Autodesk Fusion 360 part; units mm, degrees
(part 2 of 2)
extrude "CUT-SK-1100-04_M2_RAIL_TAP_A04" cut sketch "SK-1100-04_M2_RAIL_TAP_A04" against normal blind 4 contours A10 bodies 1 in component "CBP-1100_BASE_PLATE"
sketch "SK-1100-04_M2_RAIL_TAP_B04" plane through (0, 12, 0) normal (0, 1, 0) x (0, 0, 1) in component "CBP-1100_BASE_PLATE"
  circle A0 centre (60, -30) radius 0.8
  circle A1 centre (60, -45) radius 0.8
  circle A2 centre (110, 130) radius 4.5
  circle A3 centre (-110, -130) radius 4.5
  circle A4 centre (110, -130) radius 4.5
  circle A5 centre (-110, 130) radius 4.5
  line L0 (49, 74) -> (49, -74)
  line L1 (49, -74) -> (-49, -74)
  line L2 (-49, -74) -> (-49, 74)
  line L3 (-49, 74) -> (49, 74)
  line L4 (130, 150) -> (-130, 150)
  line L5 (-130, 150) -> (-130, -150)
  line L6 (-130, -150) -> (130, -150)
  line L7 (130, -150) -> (130, 150)
  circle A6 centre (-60, -60) radius 0.8
  circle A7 centre (60, -60) radius 0.8
  circle A8 centre (-60, -45) radius 0.8
  circle A9 centre (-60, -30) radius 0.8
  circle A10 centre (-60, -15) radius 0.8
  circle A11 centre (60, -15) radius 0.8
  dimension "d424" = 60
  dimension "d425" = 15
  dimension "d426" = 1.6
  measures "d424" horizontal distance of origin A11.centre
  measures "d425" vertical distance of origin A11.centre
  measures "d426" diameter of A11
extrude "CUT-SK-1100-04_M2_RAIL_TAP_B04" cut sketch "SK-1100-04_M2_RAIL_TAP_B04" against normal blind 4 contours A11 bodies 1 in component "CBP-1100_BASE_PLATE"
sketch "SK-1300-02_RAIL_CLEAR_05" plane through (0, 0, 0) normal (0, 1, 0) x (1, 0, 0) in component "CBP-1300_X_RAIL_ALIGNMENT_SHIM"
  circle A0 centre (0, 0) radius 1.15
  dimension "d429" = 2.3
  constraint coincident A0.centre origin
  measures "d429" diameter of A0
extrude "CUT-SK-1300-02_RAIL_CLEAR_05" cut sketch "SK-1300-02_RAIL_CLEAR_05" along normal blind 2 bodies 12 in component "CBP-1300_X_RAIL_ALIGNMENT_SHIM"
sketch "SK-1100-04_M2_RAIL_TAP_A05" plane through (0, 12, 0) normal (0, 1, 0) x (0, 0, 1) in component "CBP-1100_BASE_PLATE"
  circle A0 centre (-60, -15) radius 0.8
  circle A1 centre (-60, -30) radius 0.8
  circle A2 centre (-60, -45) radius 0.8
  circle A3 centre (60, -60) radius 0.8
  circle A4 centre (-60, -60) radius 0.8
  line L0 (130, 150) -> (-130, 150)
  line L1 (-130, 150) -> (-130, -150)
  line L2 (-130, -150) -> (130, -150)
  line L3 (130, -150) -> (130, 150)
  line L4 (49, 74) -> (49, -74)
  line L5 (49, -74) -> (-49, -74)
  line L6 (-49, -74) -> (-49, 74)
  line L7 (-49, 74) -> (49, 74)
  circle A5 centre (-110, 130) radius 4.5
  circle A6 centre (110, -130) radius 4.5
  circle A7 centre (-110, -130) radius 4.5
  circle A8 centre (110, 130) radius 4.5
  circle A9 centre (60, -45) radius 0.8
  circle A10 centre (60, -30) radius 0.8
  circle A11 centre (60, -15) radius 0.8
  circle A12 centre (-60, 0) radius 0.8
  dimension "d432" = 60
  dimension "d433" = 1.6
  constraint horizontal origin A12.centre
  measures "d432" horizontal distance of origin A12.centre
  measures "d433" diameter of A12
extrude "CUT-SK-1100-04_M2_RAIL_TAP_A05" cut sketch "SK-1100-04_M2_RAIL_TAP_A05" against normal blind 4 contours A12 bodies 1 in component "CBP-1100_BASE_PLATE"
sketch "SK-1100-04_M2_RAIL_TAP_B05" plane through (0, 12, 0) normal (0, 1, 0) x (0, 0, 1) in component "CBP-1100_BASE_PLATE"
  circle A0 centre (60, -15) radius 0.8
  circle A1 centre (60, -30) radius 0.8
  circle A2 centre (60, -45) radius 0.8
  circle A3 centre (110, 130) radius 4.5
  circle A4 centre (-110, -130) radius 4.5
  circle A5 centre (110, -130) radius 4.5
  circle A6 centre (-110, 130) radius 4.5
  line L0 (49, 74) -> (49, -74)
  line L1 (49, -74) -> (-49, -74)
  line L2 (-49, -74) -> (-49, 74)
  line L3 (-49, 74) -> (49, 74)
  line L4 (130, 150) -> (-130, 150)
  line L5 (-130, 150) -> (-130, -150)
  line L6 (-130, -150) -> (130, -150)
  line L7 (130, -150) -> (130, 150)
  circle A7 centre (-60, -60) radius 0.8
  circle A8 centre (60, -60) radius 0.8
  circle A9 centre (-60, -45) radius 0.8
  circle A10 centre (-60, -30) radius 0.8
  circle A11 centre (-60, -15) radius 0.8
  circle A12 centre (-60, 0) radius 0.8
  circle A13 centre (60, 0) radius 0.8
  dimension "d436" = 60
  dimension "d437" = 1.6
  constraint horizontal origin A13.centre
  measures "d436" horizontal distance of origin A13.centre
  measures "d437" diameter of A13
extrude "CUT-SK-1100-04_M2_RAIL_TAP_B05" cut sketch "SK-1100-04_M2_RAIL_TAP_B05" against normal blind 4 contours A13 bodies 1 in component "CBP-1100_BASE_PLATE"
sketch "SK-1300-02_RAIL_CLEAR_06" plane through (0, 0, 0) normal (0, 1, 0) x (1, 0, 0) in component "CBP-1300_X_RAIL_ALIGNMENT_SHIM"
  circle A0 centre (15, 0) radius 1.15
  dimension "d440" = 15
  dimension "d441" = 2.3
  constraint horizontal origin A0.centre
  measures "d440" horizontal distance of origin A0.centre
  measures "d441" diameter of A0
extrude "CUT-SK-1300-02_RAIL_CLEAR_06" cut sketch "SK-1300-02_RAIL_CLEAR_06" along normal blind 2 bodies 12 in component "CBP-1300_X_RAIL_ALIGNMENT_SHIM"
sketch "SK-1100-04_M2_RAIL_TAP_A06" plane through (0, 12, 0) normal (0, 1, 0) x (0, 0, 1) in component "CBP-1100_BASE_PLATE"
  circle A0 centre (-60, 0) radius 0.8
  circle A1 centre (-60, -15) radius 0.8
  circle A2 centre (-60, -30) radius 0.8
  circle A3 centre (-60, -45) radius 0.8
  circle A4 centre (60, -60) radius 0.8
  circle A5 centre (-60, -60) radius 0.8
  line L0 (130, 150) -> (-130, 150)
  line L1 (-130, 150) -> (-130, -150)
  line L2 (-130, -150) -> (130, -150)
  line L3 (130, -150) -> (130, 150)
  line L4 (49, 74) -> (49, -74)
  line L5 (49, -74) -> (-49, -74)
  line L6 (-49, -74) -> (-49, 74)
  line L7 (-49, 74) -> (49, 74)
  circle A6 centre (-110, 130) radius 4.5
  circle A7 centre (110, -130) radius 4.5
  circle A8 centre (-110, -130) radius 4.5
  circle A9 centre (110, 130) radius 4.5
  circle A10 centre (60, -45) radius 0.8
  circle A11 centre (60, -30) radius 0.8
  circle A12 centre (60, -15) radius 0.8
  circle A13 centre (60, 0) radius 0.8
  circle A14 centre (-60, 15) radius 0.8
  dimension "d444" = 60
  dimension "d445" = 15
  dimension "d446" = 1.6
  measures "d444" horizontal distance of origin A14.centre
  measures "d445" vertical distance of origin A14.centre
  measures "d446" diameter of A14
extrude "CUT-SK-1100-04_M2_RAIL_TAP_A06" cut sketch "SK-1100-04_M2_RAIL_TAP_A06" against normal blind 4 contours A14 bodies 1 in component "CBP-1100_BASE_PLATE"
sketch "SK-1100-04_M2_RAIL_TAP_B06" plane through (0, 12, 0) normal (0, 1, 0) x (0, 0, 1) in component "CBP-1100_BASE_PLATE"
  circle A0 centre (60, 0) radius 0.8
  circle A1 centre (60, -15) radius 0.8
  circle A2 centre (60, -30) radius 0.8
  circle A3 centre (60, -45) radius 0.8
  circle A4 centre (110, 130) radius 4.5
  circle A5 centre (-110, -130) radius 4.5
  circle A6 centre (110, -130) radius 4.5
  circle A7 centre (-110, 130) radius 4.5
  line L0 (49, 74) -> (49, -74)
  line L1 (49, -74) -> (-49, -74)
  line L2 (-49, -74) -> (-49, 74)
  line L3 (-49, 74) -> (49, 74)
  line L4 (130, 150) -> (-130, 150)
  line L5 (-130, 150) -> (-130, -150)
  line L6 (-130, -150) -> (130, -150)
  line L7 (130, -150) -> (130, 150)
  circle A8 centre (-60, -60) radius 0.8
  circle A9 centre (60, -60) radius 0.8
  circle A10 centre (-60, -45) radius 0.8
  circle A11 centre (-60, -30) radius 0.8
  circle A12 centre (-60, -15) radius 0.8
  circle A13 centre (-60, 0) radius 0.8
  circle A14 centre (-60, 15) radius 0.8
  circle A15 centre (60, 15) radius 0.8
  dimension "d449" = 60
  dimension "d450" = 15
  dimension "d451" = 1.6
  measures "d449" horizontal distance of origin A15.centre
  measures "d450" vertical distance of origin A15.centre
  measures "d451" diameter of A15
extrude "CUT-SK-1100-04_M2_RAIL_TAP_B06" cut sketch "SK-1100-04_M2_RAIL_TAP_B06" against normal blind 4 contours A15 bodies 1 in component "CBP-1100_BASE_PLATE"
sketch "SK-1300-02_RAIL_CLEAR_07" plane through (0, 0, 0) normal (0, 1, 0) x (1, 0, 0) in component "CBP-1300_X_RAIL_ALIGNMENT_SHIM"
  circle A0 centre (30, 0) radius 1.15
  dimension "d454" = 30
  dimension "d455" = 2.3
  constraint horizontal origin A0.centre
  measures "d454" horizontal distance of origin A0.centre
  measures "d455" diameter of A0
extrude "CUT-SK-1300-02_RAIL_CLEAR_07" cut sketch "SK-1300-02_RAIL_CLEAR_07" along normal blind 2 bodies 12 in component "CBP-1300_X_RAIL_ALIGNMENT_SHIM"
sketch "SK-1100-04_M2_RAIL_TAP_A07" plane through (0, 12, 0) normal (0, 1, 0) x (0, 0, 1) in component "CBP-1100_BASE_PLATE"
  circle A0 centre (-60, 15) radius 0.8
  circle A1 centre (-60, 0) radius 0.8
  circle A2 centre (-60, -15) radius 0.8
  circle A3 centre (-60, -30) radius 0.8
  circle A4 centre (-60, -45) radius 0.8
  circle A5 centre (60, -60) radius 0.8
  circle A6 centre (-60, -60) radius 0.8
  line L0 (130, 150) -> (-130, 150)
  line L1 (-130, 150) -> (-130, -150)
  line L2 (-130, -150) -> (130, -150)
  line L3 (130, -150) -> (130, 150)
  line L4 (49, 74) -> (49, -74)
  line L5 (49, -74) -> (-49, -74)
  line L6 (-49, -74) -> (-49, 74)
  line L7 (-49, 74) -> (49, 74)
  circle A7 centre (-110, 130) radius 4.5
  circle A8 centre (110, -130) radius 4.5
  circle A9 centre (-110, -130) radius 4.5
  circle A10 centre (110, 130) radius 4.5
  circle A11 centre (60, -45) radius 0.8
  circle A12 centre (60, -30) radius 0.8
  circle A13 centre (60, -15) radius 0.8
  circle A14 centre (60, 0) radius 0.8
  circle A15 centre (60, 15) radius 0.8
  circle A16 centre (-60, 30) radius 0.8
  dimension "d458" = 60
  dimension "d459" = 30
  dimension "d460" = 1.6
  measures "d458" horizontal distance of origin A16.centre
  measures "d459" vertical distance of origin A16.centre
  measures "d460" diameter of A16
extrude "CUT-SK-1100-04_M2_RAIL_TAP_A07" cut sketch "SK-1100-04_M2_RAIL_TAP_A07" against normal blind 4 contours A16 bodies 1 in component "CBP-1100_BASE_PLATE"
sketch "SK-1100-04_M2_RAIL_TAP_B07" plane through (0, 12, 0) normal (0, 1, 0) x (0, 0, 1) in component "CBP-1100_BASE_PLATE"
  circle A0 centre (60, 15) radius 0.8
  circle A1 centre (60, 0) radius 0.8
  circle A2 centre (60, -15) radius 0.8
  circle A3 centre (60, -30) radius 0.8
  circle A4 centre (60, -45) radius 0.8
  circle A5 centre (110, 130) radius 4.5
  circle A6 centre (-110, -130) radius 4.5
  circle A7 centre (110, -130) radius 4.5
  circle A8 centre (-110, 130) radius 4.5
  line L0 (49, 74) -> (49, -74)
  line L1 (49, -74) -> (-49, -74)
  line L2 (-49, -74) -> (-49, 74)
  line L3 (-49, 74) -> (49, 74)
  line L4 (130, 150) -> (-130, 150)
  line L5 (-130, 150) -> (-130, -150)
  line L6 (-130, -150) -> (130, -150)
  line L7 (130, -150) -> (130, 150)
  circle A9 centre (-60, -60) radius 0.8
  circle A10 centre (60, -60) radius 0.8
  circle A11 centre (-60, -45) radius 0.8
  circle A12 centre (-60, -30) radius 0.8
  circle A13 centre (-60, -15) radius 0.8
  circle A14 centre (-60, 0) radius 0.8
  circle A15 centre (-60, 15) radius 0.8
  circle A16 centre (-60, 30) radius 0.8
  circle A17 centre (60, 30) radius 0.8
  dimension "d463" = 60
  dimension "d464" = 30
  dimension "d465" = 1.6
  measures "d463" horizontal distance of origin A17.centre
  measures "d464" vertical distance of origin A17.centre
  measures "d465" diameter of A17
extrude "CUT-SK-1100-04_M2_RAIL_TAP_B07" cut sketch "SK-1100-04_M2_RAIL_TAP_B07" against normal blind 4 contours A17 bodies 1 in component "CBP-1100_BASE_PLATE"
sketch "SK-1300-02_RAIL_CLEAR_08" plane through (0, 0, 0) normal (0, 1, 0) x (1, 0, 0) in component "CBP-1300_X_RAIL_ALIGNMENT_SHIM"
  circle A0 centre (45, 0) radius 1.15
  dimension "d468" = 45
  dimension "d469" = 2.3
  constraint horizontal origin A0.centre
  measures "d468" horizontal distance of origin A0.centre
  measures "d469" diameter of A0
extrude "CUT-SK-1300-02_RAIL_CLEAR_08" cut sketch "SK-1300-02_RAIL_CLEAR_08" along normal blind 2 bodies 12 in component "CBP-1300_X_RAIL_ALIGNMENT_SHIM"
sketch "SK-1100-04_M2_RAIL_TAP_A08" plane through (0, 12, 0) normal (0, 1, 0) x (0, 0, 1) in component "CBP-1100_BASE_PLATE"
  circle A0 centre (-60, 30) radius 0.8
  circle A1 centre (-60, 15) radius 0.8
  circle A2 centre (-60, 0) radius 0.8
  circle A3 centre (-60, -15) radius 0.8
  circle A4 centre (-60, -30) radius 0.8
  circle A5 centre (-60, -45) radius 0.8
  circle A6 centre (60, -60) radius 0.8
  circle A7 centre (-60, -60) radius 0.8
  line L0 (130, 150) -> (-130, 150)
  line L1 (-130, 150) -> (-130, -150)
  line L2 (-130, -150) -> (130, -150)
  line L3 (130, -150) -> (130, 150)
  line L4 (49, 74) -> (49, -74)
  line L5 (49, -74) -> (-49, -74)
  line L6 (-49, -74) -> (-49, 74)
  line L7 (-49, 74) -> (49, 74)
  circle A8 centre (-110, 130) radius 4.5
  circle A9 centre (110, -130) radius 4.5
  circle A10 centre (-110, -130) radius 4.5
  circle A11 centre (110, 130) radius 4.5
  circle A12 centre (60, -45) radius 0.8
  circle A13 centre (60, -30) radius 0.8
  circle A14 centre (60, -15) radius 0.8
  circle A15 centre (60, 0) radius 0.8
  circle A16 centre (60, 15) radius 0.8
  circle A17 centre (60, 30) radius 0.8
  circle A18 centre (-60, 45) radius 0.8
  dimension "d472" = 60
  dimension "d473" = 45
  dimension "d474" = 1.6
  measures "d472" horizontal distance of origin A18.centre
  measures "d473" vertical distance of origin A18.centre
  measures "d474" diameter of A18
extrude "CUT-SK-1100-04_M2_RAIL_TAP_A08" cut sketch "SK-1100-04_M2_RAIL_TAP_A08" against normal blind 4 contours A18 bodies 1 in component "CBP-1100_BASE_PLATE"
sketch "SK-1100-04_M2_RAIL_TAP_B08" plane through (0, 12, 0) normal (0, 1, 0) x (0, 0, 1) in component "CBP-1100_BASE_PLATE"
  circle A0 centre (60, 30) radius 0.8
  circle A1 centre (60, 15) radius 0.8
  circle A2 centre (60, 0) radius 0.8
  circle A3 centre (60, -15) radius 0.8
  circle A4 centre (60, -30) radius 0.8
  circle A5 centre (60, -45) radius 0.8
  circle A6 centre (110, 130) radius 4.5
  circle A7 centre (-110, -130) radius 4.5
  circle A8 centre (110, -130) radius 4.5
  circle A9 centre (-110, 130) radius 4.5
  line L0 (49, 74) -> (49, -74)
  line L1 (49, -74) -> (-49, -74)
  line L2 (-49, -74) -> (-49, 74)
  line L3 (-49, 74) -> (49, 74)
  line L4 (130, 150) -> (-130, 150)
  line L5 (-130, 150) -> (-130, -150)
  line L6 (-130, -150) -> (130, -150)
  line L7 (130, -150) -> (130, 150)
  circle A10 centre (-60, -60) radius 0.8
  circle A11 centre (60, -60) radius 0.8
  circle A12 centre (-60, -45) radius 0.8
  circle A13 centre (-60, -30) radius 0.8
  circle A14 centre (-60, -15) radius 0.8
  circle A15 centre (-60, 0) radius 0.8
  circle A16 centre (-60, 15) radius 0.8
  circle A17 centre (-60, 30) radius 0.8
  circle A18 centre (-60, 45) radius 0.8
  circle A19 centre (60, 45) radius 0.8
  dimension "d477" = 60
  dimension "d478" = 45
  dimension "d479" = 1.6
  measures "d477" horizontal distance of origin A19.centre
  measures "d478" vertical distance of origin A19.centre
  measures "d479" diameter of A19
extrude "CUT-SK-1100-04_M2_RAIL_TAP_B08" cut sketch "SK-1100-04_M2_RAIL_TAP_B08" against normal blind 4 contours A19 bodies 1 in component "CBP-1100_BASE_PLATE"
sketch "SK-1300-02_RAIL_CLEAR_09" plane through (0, 0, 0) normal (0, 1, 0) x (1, 0, 0) in component "CBP-1300_X_RAIL_ALIGNMENT_SHIM"
  circle A0 centre (60, 0) radius 1.15
  dimension "d482" = 60
  dimension "d483" = 2.3
  constraint horizontal origin A0.centre
  measures "d482" horizontal distance of origin A0.centre
  measures "d483" diameter of A0
extrude "CUT-SK-1300-02_RAIL_CLEAR_09" cut sketch "SK-1300-02_RAIL_CLEAR_09" along normal blind 2 bodies 12 in component "CBP-1300_X_RAIL_ALIGNMENT_SHIM"
sketch "SK-1100-04_M2_RAIL_TAP_A09" plane through (0, 12, 0) normal (0, 1, 0) x (0, 0, 1) in component "CBP-1100_BASE_PLATE"
  circle A0 centre (-60, 45) radius 0.8
  circle A1 centre (-60, 30) radius 0.8
  circle A2 centre (-60, 15) radius 0.8
  circle A3 centre (-60, 0) radius 0.8
  circle A4 centre (-60, -15) radius 0.8
  circle A5 centre (-60, -30) radius 0.8
  circle A6 centre (-60, -45) radius 0.8
  circle A7 centre (60, -60) radius 0.8
  circle A8 centre (-60, -60) radius 0.8
  line L0 (130, 150) -> (-130, 150)
  line L1 (-130, 150) -> (-130, -150)
  line L2 (-130, -150) -> (130, -150)
  line L3 (130, -150) -> (130, 150)
  line L4 (49, 74) -> (49, -74)
  line L5 (49, -74) -> (-49, -74)
  line L6 (-49, -74) -> (-49, 74)
  line L7 (-49, 74) -> (49, 74)
  circle A9 centre (-110, 130) radius 4.5
  circle A10 centre (110, -130) radius 4.5
  circle A11 centre (-110, -130) radius 4.5
  circle A12 centre (110, 130) radius 4.5
  circle A13 centre (60, -45) radius 0.8
  circle A14 centre (60, -30) radius 0.8
  circle A15 centre (60, -15) radius 0.8
  circle A16 centre (60, 0) radius 0.8
  circle A17 centre (60, 15) radius 0.8
  circle A18 centre (60, 30) radius 0.8
  circle A19 centre (60, 45) radius 0.8
  circle A20 centre (-60, 60) radius 0.8
  dimension "d486" = 60
  dimension "d487" = 60
  dimension "d488" = 1.6
  measures "d486" horizontal distance of origin A20.centre
  measures "d487" vertical distance of origin A20.centre
  measures "d488" diameter of A20
extrude "CUT-SK-1100-04_M2_RAIL_TAP_A09" cut sketch "SK-1100-04_M2_RAIL_TAP_A09" against normal blind 4 contours A20 bodies 1 in component "CBP-1100_BASE_PLATE"
sketch "SK-1100-04_M2_RAIL_TAP_B09" plane through (0, 12, 0) normal (0, 1, 0) x (0, 0, 1) in component "CBP-1100_BASE_PLATE"
  circle A0 centre (60, 45) radius 0.8
  circle A1 centre (60, 30) radius 0.8
  circle A2 centre (60, 15) radius 0.8
  circle A3 centre (60, 0) radius 0.8
  circle A4 centre (60, -15) radius 0.8
  circle A5 centre (60, -30) radius 0.8
  circle A6 centre (60, -45) radius 0.8
  circle A7 centre (110, 130) radius 4.5
  circle A8 centre (-110, -130) radius 4.5
  circle A9 centre (110, -130) radius 4.5
  circle A10 centre (-110, 130) radius 4.5
  line L0 (49, 74) -> (49, -74)
  line L1 (49, -74) -> (-49, -74)
  line L2 (-49, -74) -> (-49, 74)
  line L3 (-49, 74) -> (49, 74)
  line L4 (130, 150) -> (-130, 150)
  line L5 (-130, 150) -> (-130, -150)
  line L6 (-130, -150) -> (130, -150)
  line L7 (130, -150) -> (130, 150)
  circle A11 centre (-60, -60) radius 0.8
  circle A12 centre (60, -60) radius 0.8
  circle A13 centre (-60, -45) radius 0.8
  circle A14 centre (-60, -30) radius 0.8
  circle A15 centre (-60, -15) radius 0.8
  circle A16 centre (-60, 0) radius 0.8
  circle A17 centre (-60, 15) radius 0.8
  circle A18 centre (-60, 30) radius 0.8
  circle A19 centre (-60, 45) radius 0.8
  circle A20 centre (-60, 60) radius 0.8
  circle A21 centre (60, 60) radius 0.8
  dimension "d491" = 60
  dimension "d492" = 60
  dimension "d493" = 1.6
  measures "d491" horizontal distance of origin A21.centre
  measures "d492" vertical distance of origin A21.centre
  measures "d493" diameter of A21
extrude "CUT-SK-1100-04_M2_RAIL_TAP_B09" cut sketch "SK-1100-04_M2_RAIL_TAP_B09" against normal blind 4 contours A21 bodies 1 in component "CBP-1100_BASE_PLATE"
sketch "SK-1220-01_MAST_SECTION" plane through (0, 0, 0) normal (0, 1, 0) x (1, 0, 0) in component "CBP-1220_REAR_Z_MAST"
  line L0 (10, 10) -> (-10, 10)
  line L1 (-10, 10) -> (-10, -10)
  line L2 (-10, -10) -> (10, -10)
  line L3 (10, -10) -> (10, 10)
  dimension "d505" = 20
  dimension "d506" = 20
  dimension "d507" = 10
  dimension "d508" = 10
  constraint horizontal L0
  constraint vertical L1
  constraint horizontal L2
  constraint vertical L3
  measures "d505" horizontal distance of L0.start L0.end
  measures "d506" vertical distance of L0.end L1.end
  measures "d507" horizontal distance of origin L0.start
  measures "d508" vertical distance of origin L0.start
extrude "EX-CBP-1220_MAST_SOLID_STOCK" add sketch "SK-1220-01_MAST_SECTION" along normal blind 137 separate body makes body 13 in component "CBP-1220_REAR_Z_MAST"
sketch "SK-P401-01_Z_RAIL_ENVELOPE" plane through (0, 0, 0) normal (0, 1, 0) x (1, 0, 0) in component "CBP-P401_MGN12_Z_RAIL_125_PROXY"
  line L0 (6, 4) -> (-6, 4)
  line L1 (-6, 4) -> (-6, -4)
  line L2 (-6, -4) -> (6, -4)
  line L3 (6, -4) -> (6, 4)
  dimension "d511" = 12
  dimension "d512" = 8
  dimension "d513" = 6
  dimension "d514" = 4
  constraint horizontal L0
  constraint vertical L1
  constraint horizontal L2
  constraint vertical L3
  measures "d511" horizontal distance of L0.start L0.end
  measures "d512" vertical distance of L0.end L1.end
  measures "d513" horizontal distance of origin L0.start
  measures "d514" vertical distance of origin L0.start
extrude "EX-CBP-P401_MGN12_RAIL_ENVELOPE" add sketch "SK-P401-01_Z_RAIL_ENVELOPE" along normal blind 125 separate body makes body 14 in component "CBP-P401_MGN12_Z_RAIL_125_PROXY"
sketch "SK-P402-01_Z_BLOCK_CAP" plane through (0, 0, 0) normal (0, 1, 0) x (1, 0, 0) in component "CBP-P402_MGN12H_Z_BLOCK_PROXY"
  line L0 (13.5, 2.5) -> (-13.5, 2.5)
  line L1 (-13.5, 2.5) -> (-13.5, -2.5)
  line L2 (-13.5, -2.5) -> (13.5, -2.5)
  line L3 (13.5, -2.5) -> (13.5, 2.5)
  dimension "d517" = 27
  dimension "d518" = 5
  dimension "d519" = 13.5
  dimension "d520" = 2.5
  constraint horizontal L0
  constraint vertical L1
  constraint horizontal L2
  constraint vertical L3
  measures "d517" horizontal distance of L0.start L0.end
  measures "d518" vertical distance of L0.end L1.end
  measures "d519" horizontal distance of origin L0.start
  measures "d520" vertical distance of origin L0.start
extrude "EX-CBP-P402_MGN12H_UPPER_CAP_ENVELOPE" add sketch "SK-P402-01_Z_BLOCK_CAP" along normal blind 45.4 separate body makes body 15 in component "CBP-P402_MGN12H_Z_BLOCK_PROXY"
component "10_FRAME" placed x (1, 0, 0) y (0, 1, 0) z (0, 0, 1) at (0, 0, 0)
component "20_XY_MOTION" placed x (1, 0, 0) y (0, 1, 0) z (0, 0, 1) at (0, 0, 0)
component "30_BED" placed x (1, 0, 0) y (0, 1, 0) z (0, 0, 1) at (0, 0, 0)
component "40_Z_AXIS" placed x (1, 0, 0) y (0, 1, 0) z (0, 0, 1) at (0, 0, 0)
component "50_TOOLHEAD" placed x (1, 0, 0) y (0, 1, 0) z (0, 0, 1) at (0, 0, 0)
component "60_CPAP_COOLING" placed x (1, 0, 0) y (0, 1, 0) z (0, 0, 1) at (0, 0, 0)
component "70_ELECTRONICS" placed x (1, 0, 0) y (0, 1, 0) z (0, 0, 1) at (0, 0, 0)
component "80_HARNESS" placed x (1, 0, 0) y (0, 1, 0) z (0, 0, 1) at (0, 0, 0)
component "CBP-1100_BASE_PLATE" placed x (1, 0, 0) y (0, 1, 0) z (0, 0, 1) at (0, 0, 0) in component "10_FRAME"
component "CBP-1200_40MM_Z_COLUMN" placed x (1, 0, 0) y (0, 1, 0) z (0, 0, 1) at (-160, 12, -150) in component "10_FRAME"
component "CBP-1200_40MM_Z_COLUMN" placed x (1, 0, 0) y (0, 1, 0) z (0, 0, 1) at (160, 12, -150) in component "10_FRAME"
component "CBP-1210_Z_CROSSBEAM_ENVELOPE" placed x (1, 0, 0) y (0, 1, 0) z (0, 0, 1) at (0, 252, -150) in component "10_FRAME"
component "CBP-1300_X_RAIL_ALIGNMENT_SHIM" placed x (1, 0, 0) y (0, 1, 0) z (0, 0, 1) at (0, 12, -60) in component "10_FRAME"
component "CBP-1300_X_RAIL_ALIGNMENT_SHIM" placed x (1, 0, 0) y (0, 1, 0) z (0, 0, 1) at (0, 12, 60) in component "10_FRAME"
component "CBP-1220_REAR_Z_MAST" placed x (1, 0, 0) y (0, 1, 0) z (0, 0, 1) at (0, 55, -60) in component "10_FRAME"
component "CBP-2100_CARBON_XY_STAGE" placed x (1, 0, 0) y (0, 1, 0) z (0, 0, 1) at (0, 80, 0) in component "20_XY_MOTION"
component "CBP-P201_MGN7_X_RAIL_130_PROXY" placed x (1, 0, 0) y (0, 1, 0) z (0, 0, 1) at (0, 54, -60) in component "20_XY_MOTION"
component "CBP-P201_MGN7_X_RAIL_130_PROXY" placed x (1, 0, 0) y (0, 1, 0) z (0, 0, 1) at (0, 54, 60) in component "20_XY_MOTION"
component "CBP-P202_MGN7H_X_BLOCK_PROXY" placed x (1, 0, 0) y (0, 1, 0) z (0, 0, 1) at (0, 58.8, -60) in component "20_XY_MOTION"
component "CBP-P202_MGN7H_X_BLOCK_PROXY" placed x (1, 0, 0) y (0, 1, 0) z (0, 0, 1) at (0, 58.8, 60) in component "20_XY_MOTION"
component "CBP-2200_CARBON_X_BRIDGE" placed x (1, 0, 0) y (0, 1, 0) z (0, 0, 1) at (0, 62, 0) in component "20_XY_MOTION"
component "CBP-P203_MGN7_Y_RAIL_110_PROXY" placed x (1, 0, 0) y (0, 1, 0) z (0, 0, 1) at (0, 72, 0) in component "20_XY_MOTION"
component "CBP-P204_MGN7H_Y_BLOCK_PROXY" placed x (1, 0, 0) y (0, 1, 0) z (0, 0, 1) at (0, 76.8, 0) in component "20_XY_MOTION"
component "CBP-3100_BED_SUBSTRATE" placed x (1, 0, 0) y (0, 1, 0) z (0, 0, 1) at (0, 82, 0) in component "30_BED"
component "CBP-3110_BUILD_SURFACE" placed x (1, 0, 0) y (0, 1, 0) z (0, 0, 1) at (0, 85, 0) in component "30_BED"
component "CBP-P401_MGN12_Z_RAIL_125_PROXY" placed x (1, 0, 0) y (0, 1, 0) z (0, 0, 1) at (0, 62, -46) in component "40_Z_AXIS"
component "CBP-P402_MGN12H_Z_BLOCK_PROXY" placed x (1, 0, 0) y (0, 1, 0) z (0, 0, 1) at (0, 70, -39.5) in component "40_Z_AXIS"
equation "base_x = 300 mm"
equation "base_y = 260 mm"
equation "base_t = 12 mm"
equation "d4 = base_x"
equation "d5 = base_y"
equation "d6 = base_t"
equation "base_bolt_inset = 20 mm" comment "Edge to mounting hole center"
equation "base_mount_d = 9 mm" comment "M8 clearance through holes"
equation "base_corner_r = 8 mm" comment "Outside vertical corner radius"
equation "travel_x = 64 mm" comment "Nominal useful X travel"
equation "travel_y = 40 mm" comment "Nominal useful Y travel"
equation "travel_z = 60 mm" comment "Useful nozzle Z range"
equation "bed_x = 76 mm" comment "Build surface X"
equation "bed_y = 50 mm" comment "Build surface Y"
equation "bed_t = 3 mm" comment "Development bed carrier thickness"
equation "bed_surface_t = 0.25 mm" comment "Build surface film allowance"
equation "stage_x = 112 mm" comment "Planar carrier outer X envelope; provisional"
equation "stage_y = 84 mm" comment "Planar carrier outer Y envelope; provisional"
equation "stage_t = 2 mm" comment "Carrier material thickness; provisional"
equation "guide_x = 320 mm" comment "Planar guide envelope X"
equation "guide_y = 260 mm" comment "Planar guide envelope Y"
equation "guide_t = 6 mm" comment "Guide plate stock allowance"
equation "guide_gap = 0.08 mm" comment "Prototype capture clearance; must verify fabrication"
equation "aperture_x = bed_x + travel_x + 8 mm" comment "Minimum bed and boat swept aperture X"
equation "aperture_y = bed_y + travel_y + 8 mm" comment "Minimum bed and boat swept aperture Y"
equation "tower_span = 220 mm" comment "Z tower outside support span"
equation "tower_y = 90 mm" comment "Tower axis Y from machine origin"
equation "tower_h = 180 mm" comment "Tower support height above base"
equation "tower_section = 40 mm" comment "Structural column nominal section"
equation "motor_flange = 56.4 mm" comment "Nanotec SCB5618L4204-B reference envelope only"
equation "motor_body_l = 76.5 mm" comment "Motor reference body length"
equation "motor_shaft_d = 8 mm" comment "Motor reference shaft diameter"
equation "drum_r = 25 mm" comment "Drive drum pitch radius; adjustable development parameter"
equation "belt_w = 9 mm" comment "Owned belt width; pitch and interfaces unconfirmed"
equation "anchor_x = 150 mm" comment "Drive anchor reference X offset"
equation "anchor_y = 150 mm" comment "Drive anchor reference Y offset"
equation "hose_od = 22 mm" comment "Provisional hose outside diameter; owned hose to be identified"
equation "hotend_z_envelope = 180 mm" comment "Stationary XY extrusion envelope allowance"
equation "toolhead_xy_envelope = 140 mm" comment "Multi-input extrusion service envelope"
equation "nozzle_d = 0.5 mm" comment "Maximum nozzle under retained race rules"
equation "fastener_m3_clear = 3.4 mm" comment "Ordinary M3 clearance"
equation "fastener_m5_clear = 5.5 mm" comment "Ordinary M5 clearance"
equation "fastener_m6_clear = 6.6 mm" comment "Ordinary M6 clearance"
equation "d56 = aperture_x"
equation "d57 = aperture_y"
equation "d58 = aperture_x / 2"
equation "d59 = aperture_y / 2"
equation "d60 = base_t"
equation "d62 = base_x / 2 - base_bolt_inset"
equation "d63 = base_y / 2 - base_bolt_inset"
equation "d64 = base_mount_d"
equation "d65 = base_y / 2 - base_bolt_inset"
equation "d66 = base_x / 2 - base_bolt_inset"
equation "d67 = base_t"
equation "d69 = tower_section"
equation "d70 = tower_section"
equation "d71 = tower_section / 2"
equation "d72 = tower_section / 2"
equation "d73 = tower_h"
equation "d75 = tower_span"
equation "d76 = tower_section"
equation "d77 = tower_span / 2"
equation "d78 = tower_section / 2"
equation "d79 = tower_section"
equation "d81 = stage_x"
equation "d82 = stage_y"
equation "d83 = stage_x / 2"
equation "d84 = stage_y / 2"
equation "d85 = stage_t"
equation "d87 = bed_x"
equation "d88 = bed_y"
equation "d89 = bed_x / 2"
equation "d90 = bed_y / 2"
equation "d91 = bed_t"
equation "d93 = bed_x"
equation "d94 = bed_y"
equation "d95 = bed_x / 2"
equation "d96 = bed_y / 2"
equation "d97 = bed_surface_t"
equation "x_rail_l = 130 mm" comment "X rail cut length; MGN7 candidate"
equation "y_rail_l = 110 mm" comment "Y rail cut length; MGN7 candidate"
equation "x_rail_sep = 120 mm" comment "Center-to-center X rail spacing"
equation "mgn7_rail_w = 7 mm" comment "HIWIN MGN7 rail envelope width"
equation "mgn7_rail_h = 4.8 mm" comment "HIWIN MGN7 rail envelope height"
equation "mgn7h_block_l = 30.8 mm" comment "HIWIN MGN7H block overall length"
equation "mgn7h_block_w = 17 mm" comment "HIWIN MGN7H block overall width"
equation "mgn7h_block_cap_h = 3.2 mm" comment "8 mm overall assembly height less 4.8 mm rail height; proxy cap only"
equation "bridge_w = 10 mm" comment "X moving bridge X-section"
equation "bridge_span = 140 mm" comment "X moving bridge length along machine Y"
equation "bridge_h = 10 mm" comment "X moving bridge vertical envelope"
equation "d110 = x_rail_l"
equation "d111 = mgn7_rail_w"
equation "d112 = x_rail_l / 2"
equation "d113 = mgn7_rail_w / 2"
equation "d114 = mgn7_rail_h"
equation "d116 = mgn7h_block_l"
equation "d117 = mgn7h_block_w"
equation "d118 = mgn7h_block_l / 2"
equation "d119 = mgn7h_block_w / 2"
equation "d120 = mgn7h_block_cap_h"
equation "d122 = bridge_w"
equation "d123 = bridge_span"
equation "d124 = bridge_w / 2"
equation "d125 = bridge_span / 2"
equation "d126 = bridge_h"
equation "d128 = mgn7_rail_w"
equation "d129 = y_rail_l"
equation "d130 = mgn7_rail_w / 2"
equation "d131 = y_rail_l / 2"
equation "d132 = mgn7_rail_h"
equation "d134 = mgn7h_block_w"
equation "d135 = mgn7h_block_l"
equation "d136 = mgn7h_block_w / 2"
equation "d137 = mgn7h_block_l / 2"
equation "d138 = mgn7h_block_cap_h"
equation "x_shim_w = 12 mm" comment "Machined X-rail support strip width across machine Y"
equation "x_shim_t = 2 mm" comment "Matched X-rail shim thickness; reference until measured"
equation "d142 = x_rail_l"
equation "d143 = x_shim_w"
equation "d144 = x_rail_l / 2"
equation "d145 = x_shim_w / 2"
equation "d146 = x_shim_t"
equation "tower_center_span = 180 mm" comment "Center-to-center distance of two rear Z columns"
equation "mgn7_rail_hole_d = 2.3 mm" comment "HIWIN MGN7 rail mounting through hole diameter"
equation "mgn7_rail_pitch = 15 mm" comment "HIWIN MGN7 rail mounting hole pitch"
equation "d152 = mgn7_rail_hole_d"
equation "d154 = mgn7_rail_hole_d"
equation "d156 = mgn7_rail_hole_d"
equation "d158 = mgn7_rail_hole_d"
equation "d159 = mgn7_rail_hole_d"
equation "d161 = mgn7_rail_hole_d"
equation "d163 = mgn7_rail_hole_d"
equation "d165 = mgn7_rail_hole_d"
equation "d167 = mgn7_rail_hole_d"
equation "d168 = mgn7_rail_h"
equation "d171 = mgn7_rail_hole_d"
equation "d173 = mgn7_rail_hole_d"
equation "d175 = mgn7_rail_hole_d"
equation "d176 = mgn7_rail_hole_d"
equation "d178 = mgn7_rail_hole_d"
equation "d180 = mgn7_rail_hole_d"
equation "d182 = mgn7_rail_hole_d"
equation "d183 = mgn7_rail_h"
equation "mgn7_counterbore_d = 4.2 mm" comment "HIWIN MGN7 rail counterbore diameter"
equation "mgn7_counterbore_depth = 2.4 mm" comment "HIWIN MGN7 rail counterbore depth from top"
equation "d188 = mgn7_counterbore_d"
equation "d190 = mgn7_counterbore_d"
equation "d192 = mgn7_counterbore_d"
equation "d194 = mgn7_counterbore_d"
equation "d195 = mgn7_counterbore_d"
equation "d197 = mgn7_counterbore_d"
equation "d199 = mgn7_counterbore_d"
equation "d201 = mgn7_counterbore_d"
equation "d203 = mgn7_counterbore_d"
equation "d207 = mgn7_counterbore_d"
equation "d209 = mgn7_counterbore_d"
equation "d211 = mgn7_counterbore_d"
equation "d212 = mgn7_counterbore_d"
equation "d214 = mgn7_counterbore_d"
equation "d216 = mgn7_counterbore_d"
equation "d218 = mgn7_counterbore_d"
equation "d221 = -mgn7_counterbore_depth"
equation "d223 = -mgn7_counterbore_depth"
equation "mgn7h_tap_pilot_d = 1.6 mm" comment "Pilot for nominal M2 tap, simplified"
equation "mgn7h_mount_thread_depth = 2.5 mm" comment "HIWIN MGN7H block M2 thread depth"
equation "mgn7h_mount_B = 12 mm" comment "HIWIN MGN7H mounting transverse spacing"
equation "mgn7h_mount_C = 13 mm" comment "HIWIN MGN7H mounting longitudinal spacing"
equation "d231 = mgn7h_tap_pilot_d"
equation "d232 = -mgn7h_mount_thread_depth"
equation "d236 = mgn7h_tap_pilot_d"
equation "d237 = -mgn7h_mount_thread_depth"
equation "d241 = mgn7h_tap_pilot_d"
equation "d242 = -mgn7h_mount_thread_depth"
equation "d246 = mgn7h_tap_pilot_d"
equation "d247 = -mgn7h_mount_thread_depth"
equation "d251 = mgn7h_tap_pilot_d"
equation "d252 = -mgn7h_mount_thread_depth"
equation "d256 = mgn7h_tap_pilot_d"
equation "d257 = -mgn7h_mount_thread_depth"
equation "d261 = mgn7h_tap_pilot_d"
equation "d262 = -mgn7h_mount_thread_depth"
equation "d266 = mgn7h_tap_pilot_d"
equation "d267 = -mgn7h_mount_thread_depth"
equation "bridge_pad_w = 22 mm" comment "Monolithic bridge end pad width along X"
equation "bridge_pad_l = 24 mm" comment "Monolithic bridge end pad length along Y"
equation "d271 = bridge_pad_w"
equation "d272 = bridge_pad_l"
equation "d273 = bridge_pad_w / 2"
equation "d274 = x_rail_sep / 2 + bridge_pad_l / 2"
equation "d275 = bridge_h"
equation "d277 = bridge_pad_w"
equation "d278 = bridge_pad_l"
equation "d279 = bridge_pad_w / 2"
equation "d280 = x_rail_sep / 2 + bridge_pad_l / 2"
equation "d281 = bridge_h"
equation "m2_carriage_clearance_d = 2.2 mm" comment "M2 clearance in bridge and stage"
equation "d286 = m2_carriage_clearance_d"
equation "d287 = bridge_h"
equation "d291 = m2_carriage_clearance_d"
equation "d292 = bridge_h"
equation "d296 = m2_carriage_clearance_d"
equation "d297 = bridge_h"
equation "d301 = m2_carriage_clearance_d"
equation "d302 = bridge_h"
equation "d306 = m2_carriage_clearance_d"
equation "d307 = bridge_h"
equation "d311 = m2_carriage_clearance_d"
equation "d312 = bridge_h"
equation "d316 = m2_carriage_clearance_d"
equation "d317 = bridge_h"
equation "d321 = m2_carriage_clearance_d"
equation "d322 = bridge_h"
equation "d326 = m2_carriage_clearance_d"
equation "d327 = stage_t"
equation "d331 = m2_carriage_clearance_d"
equation "d332 = stage_t"
equation "d336 = m2_carriage_clearance_d"
equation "d337 = stage_t"
equation "d341 = m2_carriage_clearance_d"
equation "d342 = stage_t"
equation "d345 = m2_carriage_clearance_d"
equation "d346 = bridge_h"
equation "d349 = m2_carriage_clearance_d"
equation "d350 = bridge_h"
equation "d353 = m2_carriage_clearance_d"
equation "d354 = bridge_h"
equation "d356 = m2_carriage_clearance_d"
equation "d357 = bridge_h"
equation "d360 = m2_carriage_clearance_d"
equation "d361 = bridge_h"
equation "d364 = m2_carriage_clearance_d"
equation "d365 = bridge_h"
equation "d368 = m2_carriage_clearance_d"
equation "d369 = bridge_h"
equation "base_m2_tap_pilot_d = 1.6 mm" comment "Pilot for M2 rail screw tapped into aluminum base"
equation "base_m2_tap_depth = 4 mm" comment "Blind M2 rail screw thread depth in base"
equation "d374 = mgn7_rail_hole_d"
equation "d375 = x_shim_t"
equation "d379 = base_m2_tap_pilot_d"
equation "d380 = -base_m2_tap_depth"
equation "d384 = base_m2_tap_pilot_d"
equation "d385 = -base_m2_tap_depth"
equation "d388 = mgn7_rail_hole_d"
equation "d389 = x_shim_t"
equation "d393 = base_m2_tap_pilot_d"
equation "d394 = -base_m2_tap_depth"
equation "d398 = base_m2_tap_pilot_d"
equation "d399 = -base_m2_tap_depth"
equation "d402 = mgn7_rail_hole_d"
equation "d403 = x_shim_t"
equation "d407 = base_m2_tap_pilot_d"
equation "d408 = -base_m2_tap_depth"
equation "d412 = base_m2_tap_pilot_d"
equation "d413 = -base_m2_tap_depth"
equation "d416 = mgn7_rail_hole_d"
equation "d417 = x_shim_t"
equation "d421 = base_m2_tap_pilot_d"
equation "d422 = -base_m2_tap_depth"
equation "d426 = base_m2_tap_pilot_d"
equation "d427 = -base_m2_tap_depth"
equation "d429 = mgn7_rail_hole_d"
equation "d430 = x_shim_t"
equation "d433 = base_m2_tap_pilot_d"
equation "d434 = -base_m2_tap_depth"
equation "d437 = base_m2_tap_pilot_d"
equation "d438 = -base_m2_tap_depth"
equation "d441 = mgn7_rail_hole_d"
equation "d442 = x_shim_t"
equation "d446 = base_m2_tap_pilot_d"
equation "d447 = -base_m2_tap_depth"
equation "d451 = base_m2_tap_pilot_d"
equation "d452 = -base_m2_tap_depth"
equation "d455 = mgn7_rail_hole_d"
equation "d456 = x_shim_t"
equation "d460 = base_m2_tap_pilot_d"
equation "d461 = -base_m2_tap_depth"
equation "d465 = base_m2_tap_pilot_d"
equation "d466 = -base_m2_tap_depth"
equation "d469 = mgn7_rail_hole_d"
equation "d470 = x_shim_t"
equation "d474 = base_m2_tap_pilot_d"
equation "d475 = -base_m2_tap_depth"
equation "d479 = base_m2_tap_pilot_d"
equation "d480 = -base_m2_tap_depth"
equation "d483 = mgn7_rail_hole_d"
equation "d484 = x_shim_t"
equation "d488 = base_m2_tap_pilot_d"
equation "d489 = -base_m2_tap_depth"
equation "d493 = base_m2_tap_pilot_d"
equation "d494 = -base_m2_tap_depth"
equation "z_mast_w = 20 mm" comment "Central fixed Z mast X width"
equation "z_mast_depth = 20 mm" comment "Central fixed Z mast front-back depth"
equation "z_mast_h = 137 mm" comment "Mast from machine height 55 to 192 mm"
equation "z_rail_l = 125 mm" comment "Development MGN12 Z rail length"
equation "mgn12_rail_w = 12 mm" comment "HIWIN MGN12 rail width"
equation "mgn12_rail_h = 8 mm" comment "HIWIN MGN12 rail height"
equation "mgn12h_block_w = 27 mm" comment "HIWIN MGN12H block width"
equation "mgn12h_block_l = 45.4 mm" comment "HIWIN MGN12H block length"
equation "mgn12h_cap_depth = 5 mm" comment "Proxy cap: 13 mm assembly less 8 mm rail"
equation "d505 = z_mast_w"
equation "d506 = z_mast_depth"
equation "d507 = z_mast_w / 2"
equation "d508 = z_mast_depth / 2"
equation "d509 = z_mast_h"
equation "d511 = mgn12_rail_w"
equation "d512 = mgn12_rail_h"
equation "d513 = mgn12_rail_w / 2"
equation "d514 = mgn12_rail_h / 2"
equation "d515 = z_rail_l"
equation "d517 = mgn12h_block_w"
equation "d518 = mgn12h_cap_depth"
equation "d519 = mgn12h_block_w / 2"
equation "d520 = mgn12h_cap_depth / 2"
equation "d521 = mgn12h_block_l"
named bodies: "CBP-1100_BASE_STOCK", "CBP-1200_COLUMN_ENVELOPE", "CBP-1210_CROSSBEAM_ENVELOPE", "CBP-2100_2MM_STAGE_STOCK", "CBP-3100_BED_SUBSTRATE_STOCK", "CBP-3110_BUILD_SURFACE_FILM", "CBP-P201_X_RAIL_ENVELOPE", "CBP-P202_X_BLOCK_UPPER_ENVELOPE", "CBP-2200_BRIDGE_STOCK", "CBP-P203_Y_RAIL_ENVELOPE", "CBP-P204_Y_BLOCK_UPPER_ENVELOPE", "CBP-1300_SHIM_STOCK", "CBP-1220_MAST_SOLID_STOCK", "CBP-P401_MGN12_RAIL_ENVELOPE", "CBP-P402_MGN12H_UPPER_CAP_ENVELOPE"
